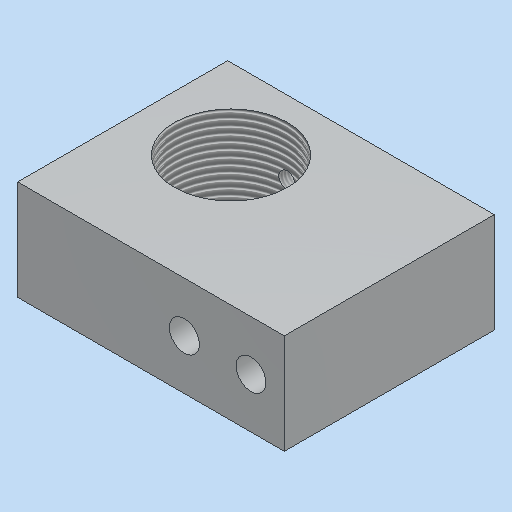
# Autodesk Inventor part: MM0948AN160_G01_112
Saved by Autodesk Inventor 2023.3 (Build 273359000, 359)
## iProperties
RuleStatus: InUse
Part Number: MM0948AN160_G01_112
Material: 3.3547 AlMg4,5Mn0,7 - AW 5083
Description: =<RBPARTNOTITLE2>
Document SubType Name: Modeling
Designer: ric7an
Mass: 37.9505 g
Surface Area: 60.0297 cm^2
Volume: 14.0557 cm^3
Density: 2.7 g/cm^3
Appearance: Aluminium AnP
Created: 2023-03-23
BeforeDocSave0: file://AnP_Ansicht_ausrichten
RBDOCUMENTTYPE: DRF
RBDOCUMENTVERSION: 00
RBDRAWINGMAINSCALE: 1:1
RBDRAWINGMISSINGSPEC: --
RBDRAWINGVOLUME: --
RBGBEDGESIN1: +0,5
RBGBEDGESIN2: +0,2
RBGBEDGESOUT1: -0,3
RBGBEDGESOUT2: -0,1
RBMATERIAL: =<Material>
RBMATMEETS: --
RBMATNO: =<Part Number>
RBPARTMADEOF: 15 x 36,5 x 40 (FM)
RBPARTNO: SIEHE MNR
RBPARTNOTITLE1: manufactured part
RBPARTNOTITLE2: Anfertigungsteil
RBPARTSAFETYINDICATOR: --
RBSURFACE: anodised colourless
RBSURFACE2: eloxiert farblos
RBZEDGESNORM: ISO13715:2002-06
RBZGENDIMCLASS: m
RBZGENDIMNORM: ISO 2768-1:1989-11
RBZGENGEOCLASS: H
RBZGENGEONORM: ISO 2768-2:1989-11
RBZSURFACENORM: ISO13D2:2002-02
RBZTOLERANCENORM: ISO 14405-1:2010-12
AnP_Material: =<Material>
AnP_TemplVers: 20190222
AnP_Kategorie: 1
MaxAbmaße: 15 x 36,5 x 40 (FM)
AnP_Kommentar_aktuell: =<Comments>
AnP_Material_aktuell: =<Material>
Author: FH/Wi
Keywords: =<RBPARTMADEOF>
Comments: =<RBSURFACE2>
Revision Number: 01
Autodesk Inventor part; units mm, degrees
ref_plane "YZ Plane" through (0, 0, 0) normal (1, 0, 0) x (0, 1, 0)
ref_plane "XZ Plane" through (0, 0, 0) normal (0, 1, 0) x (-1, 0, 0)
ref_plane "XY Plane" through (0, 0, 0) normal (0, 0, 1) x (1, 0, 0)
sketch "Skizze1" plane through (0, 0, 0) normal (0, 0, 1) x (1, 0, 0)
  line L0 (-20, 0) -> (20, 0)
  line L1 (20, 0) -> (20, 31.5)
  line L2 (20, 31.5) -> (-20, 31.5)
  line L3 (-20, 31.5) -> (-20, 0)
  line L4 (0, 37.8) -> (0, -6.3) projected
  line L5 (-28, 0) -> (28, 0) projected
  dimension "d0" = 31.5
  dimension "d1" = 40
  constraints: 8 end point, 2 parallel, 1 collinear, 1 horizontal, 1 perpendicular, 1 other
  measures "d0" distance of L0.end L1.end
  measures "d1" distance of L1.end L2.end
extrude "Extrusion1" add sketch "Skizze1" along normal blind 15
sketch "Skizze3" plane through (0, 0, 0) normal (0, 0, -1) x (-1, 0, 0)
  line L0 (0, 0) -> (-20, 0) projected
  line L1 (-20, 0) -> (-20, 31.5) projected
  line L2 (-20, 31.5) -> (20, 31.5) projected
  line L3 (20, 31.5) -> (20, 0) projected
  point P0 (7.5, 19.5)
  dimension "d43" = 12
  dimension "d45" = 12.5
  measures "d43" distance from line of point (7.5, 19.5) L2
  measures "d45" distance from line of L3 point (7.5, 19.5)
hole "Bohrung1" at (-7.5, 19.5, 0) direction (0, 0, 1) diameter 16.9175 end through all thread size "M18x1" class "6H" standard "ISO Metric profile"
sketch "Skizze4" plane through (-20, 31.5, 15) normal (0, 1, 0) x (1, 0, 0)
  line L0 (48, 15) -> (-8, 15) projected
  line L1 (40, 0) -> (0, 0) projected
  line L2 (40, 15) -> (40, 0) projected
  line L3 (0, 15) -> (0, 0) projected
  point P0 (20, 15)
  point P1 (25, 7.5)
  point P2 (35, 7.5)
  point P3 (40, 7.5)
  dimension "d14" = 7.5
  dimension "d15" = 10
  dimension "d49" = 25
  constraints: 1 horizontal alignment, 1 midpoint
  measures "d14" distance from line of L1 point (25, 7.5)
  measures "d15" distance of point (35, 7.5) point (25, 7.5)
  measures "d49" distance from line of L3 point (25, 7.5)
hole "Bohrung2" at (5, 31.5, 7.5) at (15, 31.5, 7.5) direction (0, -1, 0) diameter 4.5 end through all counterbore diameter 8 counterbore depth 6.6 clearance for "Inbusschraube ISO 4762  versenkt" size "M4" standard "ISO"
sketch "Skizze7" plane through (-20, 31.5, 0) normal (0, -1, 0) x (1, 0, 0)
  line L0 (-8, 0) -> (48, 0) projected
  line L1 (0, 0) -> (0, 15) projected
  point P0 (20, 0)
  point P1 (12.5, 7.5)
  point P2 (5, 7.5)
  point P3 (0, 7.5)
  dimension "d46" = 12.5
  constraints: 2 horizontal alignment, 1 midpoint
  measures "d46" distance from line of L1 point (12.5, 7.5)
hole "Bohrung4" at (-7.5, 31.5, 7.5) direction (0, -1, 0) diameter 2.459 depth 5 tip angle 118 thread size "M3x0.5" designation "M3" class "6H" standard "ISO Metric profile"
